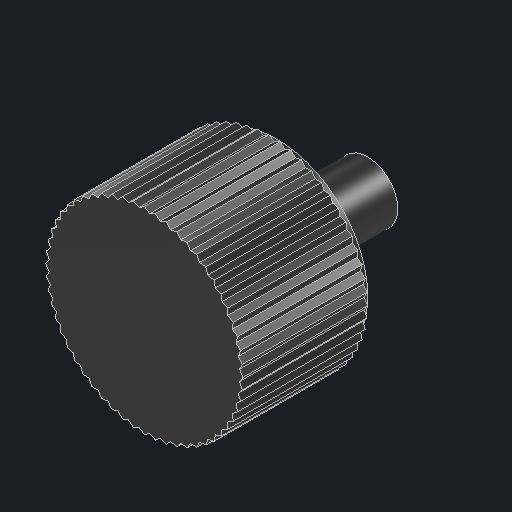
# Autodesk Inventor part: worm_knob
Saved by Autodesk Inventor 2027.1 (Build 311270010, 270A)
## iProperties
Created: 2026-11-03
Part Number: worm_knob
Material: Generic
Description: Worm slow-motion knob ~29.6 x 19.9 (length measured) on a 13.6 mm spacer; inner face 15.07 mm off the block (measured)
Document SubType Name: Modeling
Designer: Claude (from photos)
Density: 1 g/cm^3
Appearance: Glossy - Black
Author: alexg
Autodesk Inventor part; units mm, degrees
ref_plane "Work Plane1" through (0, 0, 1.5) normal (0, 0, 1) x (1, 0, 0)
sketch "Spacer sketch" plane through (0, 0, 1.5) normal (0, 0, 1) x (1, 0, 0)
  circle A0 centre (0, 0) radius 4.5
  circle A1 centre (0, 0) radius 3.05
  constraints: 2 centre point
extrude "Spacer" add sketch "Spacer sketch" along normal blind 13.6
ref_plane "Work Plane2" through (0, 0, 15.1) normal (0, 0, 1) x (1, 0, 0)
sketch "Inner chamfer step sketch" plane through (0, 0, 15.1) normal (0, 0, 1) x (1, 0, 0)
  circle A0 centre (0, 0) radius 13.6
  constraints: 1 centre point
extrude "Inner chamfer step" add sketch "Inner chamfer step sketch" along normal blind 1.2
ref_plane "Work Plane3" through (0, 0, 16.3) normal (0, 0, 1) x (1, 0, 0)
sketch "Knurled body sketch" plane through (0, 0, 16.3) normal (0, 0, 1) x (1, 0, 0)
  line L0 (14.8, 0) -> (14.2775, 0.8018)
  line L1 (14.2775, 0.8018) -> (14.7069, 1.6571)
  line L2 (14.7069, 1.6571) -> (14.098, 2.3953)
  line L3 (14.098, 2.3953) -> (14.4289, 3.2933)
  line L4 (14.4289, 3.2933) -> (13.7411, 3.9587)
  line L5 (13.7411, 3.9587) -> (13.9695, 4.8881)
  line L6 (13.9695, 4.8881) -> (13.2115, 5.4724)
  line L7 (13.2115, 5.4724) -> (13.3343, 6.4215)
  line L8 (13.3343, 6.4215) -> (12.5157, 6.9172)
  line L9 (12.5157, 6.9172) -> (12.5315, 7.8741)
  line L10 (12.5315, 7.8741) -> (11.6625, 8.275)
  line L11 (11.6625, 8.275) -> (11.5711, 9.2276)
  line L12 (11.5711, 9.2276) -> (10.6627, 9.5288)
  line L13 (10.6627, 9.5288) -> (10.4652, 10.4652)
  line L14 (10.4652, 10.4652) -> (9.5288, 10.6627)
  line L15 (9.5288, 10.6627) -> (9.2276, 11.5711)
  line L16 (9.2276, 11.5711) -> (8.275, 11.6625)
  line L17 (8.275, 11.6625) -> (7.8741, 12.5315)
  line L18 (7.8741, 12.5315) -> (6.9172, 12.5157)
  line L19 (6.9172, 12.5157) -> (6.4215, 13.3343)
  line L20 (6.4215, 13.3343) -> (5.4724, 13.2115)
  line L21 (5.4724, 13.2115) -> (4.8881, 13.9695)
  line L22 (4.8881, 13.9695) -> (3.9587, 13.7411)
  line L23 (3.9587, 13.7411) -> (3.2933, 14.4289)
  line L24 (3.2933, 14.4289) -> (2.3953, 14.098)
  line L25 (2.3953, 14.098) -> (1.6571, 14.7069)
  line L26 (1.6571, 14.7069) -> (0.8018, 14.2775)
  line L27 (0.8018, 14.2775) -> (0, 14.8)
  line L28 (0, 14.8) -> (-0.8018, 14.2775)
  line L29 (-0.8018, 14.2775) -> (-1.6571, 14.7069)
  line L30 (-1.6571, 14.7069) -> (-2.3953, 14.098)
  line L31 (-2.3953, 14.098) -> (-3.2933, 14.4289)
  line L32 (-3.2933, 14.4289) -> (-3.9587, 13.7411)
  line L33 (-3.9587, 13.7411) -> (-4.8881, 13.9695)
  line L34 (-4.8881, 13.9695) -> (-5.4724, 13.2115)
  line L35 (-5.4724, 13.2115) -> (-6.4215, 13.3343)
  line L36 (-6.4215, 13.3343) -> (-6.9172, 12.5157)
  line L37 (-6.9172, 12.5157) -> (-7.8741, 12.5315)
  line L38 (-7.8741, 12.5315) -> (-8.275, 11.6625)
  line L39 (-8.275, 11.6625) -> (-9.2276, 11.5711)
  line L40 (-9.2276, 11.5711) -> (-9.5288, 10.6627)
  line L41 (-9.5288, 10.6627) -> (-10.4652, 10.4652)
  line L42 (-10.4652, 10.4652) -> (-10.6627, 9.5288)
  line L43 (-10.6627, 9.5288) -> (-11.5711, 9.2276)
  line L44 (-11.5711, 9.2276) -> (-11.6625, 8.275)
  line L45 (-11.6625, 8.275) -> (-12.5315, 7.8741)
  line L46 (-12.5315, 7.8741) -> (-12.5157, 6.9172)
  line L47 (-12.5157, 6.9172) -> (-13.3343, 6.4215)
  line L48 (-13.3343, 6.4215) -> (-13.2115, 5.4724)
  line L49 (-13.2115, 5.4724) -> (-13.9695, 4.8881)
  line L50 (-13.9695, 4.8881) -> (-13.7411, 3.9587)
  line L51 (-13.7411, 3.9587) -> (-14.4289, 3.2933)
  line L52 (-14.4289, 3.2933) -> (-14.098, 2.3953)
  line L53 (-14.098, 2.3953) -> (-14.7069, 1.6571)
  line L54 (-14.7069, 1.6571) -> (-14.2775, 0.8018)
  line L55 (-14.2775, 0.8018) -> (-14.8, 0)
  line L56 (-14.8, 0) -> (-14.2775, -0.8018)
  line L57 (-14.2775, -0.8018) -> (-14.7069, -1.6571)
  line L58 (-14.7069, -1.6571) -> (-14.098, -2.3953)
  line L59 (-14.098, -2.3953) -> (-14.4289, -3.2933)
  line L60 (-14.4289, -3.2933) -> (-13.7411, -3.9587)
  line L61 (-13.7411, -3.9587) -> (-13.9695, -4.8881)
  line L62 (-13.9695, -4.8881) -> (-13.2115, -5.4724)
  line L63 (-13.2115, -5.4724) -> (-13.3343, -6.4215)
  line L64 (-13.3343, -6.4215) -> (-12.5157, -6.9172)
  line L65 (-12.5157, -6.9172) -> (-12.5315, -7.8741)
  line L66 (-12.5315, -7.8741) -> (-11.6625, -8.275)
  line L67 (-11.6625, -8.275) -> (-11.5711, -9.2276)
  line L68 (-11.5711, -9.2276) -> (-10.6627, -9.5288)
  line L69 (-10.6627, -9.5288) -> (-10.4652, -10.4652)
  line L70 (-10.4652, -10.4652) -> (-9.5288, -10.6627)
  line L71 (-9.5288, -10.6627) -> (-9.2276, -11.5711)
  line L72 (-9.2276, -11.5711) -> (-8.275, -11.6625)
  line L73 (-8.275, -11.6625) -> (-7.8741, -12.5315)
  line L74 (-7.8741, -12.5315) -> (-6.9172, -12.5157)
  line L75 (-6.9172, -12.5157) -> (-6.4215, -13.3343)
  line L76 (-6.4215, -13.3343) -> (-5.4724, -13.2115)
  line L77 (-5.4724, -13.2115) -> (-4.8881, -13.9695)
  line L78 (-4.8881, -13.9695) -> (-3.9587, -13.7411)
  line L79 (-3.9587, -13.7411) -> (-3.2933, -14.4289)
  line L80 (-3.2933, -14.4289) -> (-2.3953, -14.098)
  line L81 (-2.3953, -14.098) -> (-1.6571, -14.7069)
  line L82 (-1.6571, -14.7069) -> (-0.8018, -14.2775)
  line L83 (-0.8018, -14.2775) -> (0, -14.8)
  line L84 (0, -14.8) -> (0.8018, -14.2775)
  line L85 (0.8018, -14.2775) -> (1.6571, -14.7069)
  line L86 (1.6571, -14.7069) -> (2.3953, -14.098)
  line L87 (2.3953, -14.098) -> (3.2933, -14.4289)
  line L88 (3.2933, -14.4289) -> (3.9587, -13.7411)
  line L89 (3.9587, -13.7411) -> (4.8881, -13.9695)
  line L90 (4.8881, -13.9695) -> (5.4724, -13.2115)
  line L91 (5.4724, -13.2115) -> (6.4215, -13.3343)
  line L92 (6.4215, -13.3343) -> (6.9172, -12.5157)
  line L93 (6.9172, -12.5157) -> (7.8741, -12.5315)
  line L94 (7.8741, -12.5315) -> (8.275, -11.6625)
  line L95 (8.275, -11.6625) -> (9.2276, -11.5711)
  line L96 (9.2276, -11.5711) -> (9.5288, -10.6627)
  line L97 (9.5288, -10.6627) -> (10.4652, -10.4652)
  line L98 (10.4652, -10.4652) -> (10.6627, -9.5288)
  line L99 (10.6627, -9.5288) -> (11.5711, -9.2276)
  line L100 (11.5711, -9.2276) -> (11.6625, -8.275)
  line L101 (11.6625, -8.275) -> (12.5315, -7.8741)
  line L102 (12.5315, -7.8741) -> (12.5157, -6.9172)
  line L103 (12.5157, -6.9172) -> (13.3343, -6.4215)
  line L104 (13.3343, -6.4215) -> (13.2115, -5.4724)
  line L105 (13.2115, -5.4724) -> (13.9695, -4.8881)
  line L106 (13.9695, -4.8881) -> (13.7411, -3.9587)
  line L107 (13.7411, -3.9587) -> (14.4289, -3.2933)
  line L108 (14.4289, -3.2933) -> (14.098, -2.3953)
  line L109 (14.098, -2.3953) -> (14.7069, -1.6571)
  line L110 (14.7069, -1.6571) -> (14.2775, -0.8018)
  line L111 (14.2775, -0.8018) -> (14.8, 0)
  constraints: 224 end point
extrude "Knurled body" add sketch "Knurled body sketch" along normal blind 18.7
ref_plane "Work Plane4" through (0, 0, 15.1) normal (0, 0, 1) x (1, 0, 0)
sketch "Shaft bore sketch" plane through (0, 0, 15.1) normal (0, 0, 1) x (1, 0, 0)
  circle A0 centre (0, 0) radius 3.05
  constraints: 1 centre point
extrude "Shaft bore" cut sketch "Shaft bore sketch" along normal blind 10
body "Solid1"
